sumidero (Autodesk Fusion 360 design; units mm, degrees)
part number: 2026-11-08-17-53-29-984
part number: 2026-11-08-17-55-23-853
part number: 2026-11-08-18-24-42-982
part number: 2026-11-08-18-26-39-460
part number: 2026-11-11-10-27-06-678
Autodesk Fusion 360 part; units mm, degrees
(part 1 of 2)
sketch "Sk_Exterior" plane through (0, 0, 0) normal (0, 0, 1) x (1, 0, 0) in component "Caja"
  line L0 (-70, -44) -> (70, -44)
  line L1 (70, -44) -> (70, 44)
  line L2 (70, 44) -> (-70, 44)
  line L3 (-70, 44) -> (-70, -44)
  dimension "d106" = 140
  dimension "d107" = 88
  dimension "d108" = 70
  dimension "d109" = 44
  measures "d106" horizontal distance of L0.start L0.end
  measures "d107" vertical distance of L0.start L2.end
  measures "d108" horizontal distance of origin L0.start
  measures "d109" vertical distance of origin L0.start
extrude "Ext_Cuerpo" add sketch "Sk_Exterior" along normal blind 95 makes body 1 in component "Caja"
fillet "Fillet_Exterior" radius 3 4 edges at (-70, 44, 47.5) (70, 44, 47.5) (70, -44, 47.5) (-70, -44, 47.5) on bodies 1 in component "Caja"
ref_plane "WorkPlane1" through (0, 0, 4) normal (0, 0, 1) x (1, 0, 0) in component "Caja"
sketch "Sk_Cavidad" plane through (0, 0, 4) normal (0, 0, 1) x (1, 0, 0) in component "Caja"
  line L0 (-65, -39) -> (65, -39)
  line L1 (65, -39) -> (65, 39)
  line L2 (65, 39) -> (-65, 39)
  line L3 (-65, 39) -> (-65, -39)
  dimension "d116" = 130
  dimension "d117" = 78
  dimension "d118" = 65
  dimension "d119" = 39
  measures "d116" horizontal distance of L0.start L0.end
  measures "d117" vertical distance of L0.start L2.end
  measures "d118" horizontal distance of origin L0.start
  measures "d119" vertical distance of origin L0.start
extrude "Cut_Cavidad" cut sketch "Sk_Cavidad" along normal blind 91 bodies 1 in component "Caja"
fillet "Fillet_Cavidad" radius 3 4 edges at (65, 39, 49.5) (-65, 39, 49.5) (65, -39, 49.5) (-65, -39, 49.5) on bodies 1 in component "Caja"
ref_plane "WorkPlane2" through (0, 0, 95) normal (0, 0, 1) x (1, 0, 0) in component "Caja"
sketch "Sk_Junta" plane through (0, 0, 95) normal (0, 0, 1) x (1, 0, 0) in component "Caja"
  line L0 (-68.8, -42.8) -> (68.8, -42.8)
  line L1 (68.8, -42.8) -> (68.8, 42.8)
  line L2 (68.8, 42.8) -> (-68.8, 42.8)
  line L3 (-68.8, 42.8) -> (-68.8, -42.8)
  line L4 (-66.2, -40.2) -> (66.2, -40.2)
  line L5 (66.2, -40.2) -> (66.2, 40.2)
  line L6 (66.2, 40.2) -> (-66.2, 40.2)
  line L7 (-66.2, 40.2) -> (-66.2, -40.2)
  dimension "d126" = 137.6
  dimension "d127" = 85.6
  dimension "d128" = 68.8
  dimension "d129" = 42.8
  dimension "d130" = 132.4
  dimension "d131" = 80.4
  dimension "d132" = 66.2
  dimension "d133" = 40.2
  measures "d126" horizontal distance of L0.start L0.end
  measures "d127" vertical distance of L0.start L2.end
  measures "d128" horizontal distance of origin L0.start
  measures "d129" vertical distance of origin L0.start
  measures "d130" horizontal distance of L4.start L4.end
  measures "d131" vertical distance of L4.start L6.end
  measures "d132" horizontal distance of origin L4.start
  measures "d133" vertical distance of origin L4.start
extrude "Cut_Junta" cut sketch "Sk_Junta" against normal blind 1.5 bodies 1 in component "Caja"
fillet "Fillet_Junta" radius 3.6 4 edges at (68.8, -42.8, 94.25) (-68.8, -42.8, 94.25) (68.8, 42.8, 94.25) (-68.8, 42.8, 94.25) on bodies 1 in component "Caja"
fillet "Fillet_Junta" radius 1 4 edges at (66.2, 40.2, 94.25) (-66.2, 40.2, 94.25) (66.2, -40.2, 94.25) (-66.2, -40.2, 94.25) on bodies 1 in component "Caja"
sketch "Sk_Oreja_1" plane through (0, 0, 0) normal (0, 0, 1) x (1, 0, 0) in component "Caja"
  line L0 (58, 43) -> (70, 43)
  line L1 (70, 43) -> (70, 56)
  line L2 (70, 56) -> (58, 56)
  line L3 (58, 56) -> (58, 43)
  dimension "d140" = 12
  dimension "d141" = 13
  dimension "d142" = 58
  dimension "d143" = 43
  measures "d140" horizontal distance of L0.start L0.end
  measures "d141" vertical distance of L0.start L2.end
  measures "d142" horizontal distance of origin L0.start
  measures "d143" vertical distance of origin L0.start
extrude "Oreja_1" add sketch "Sk_Oreja_1" along normal blind 95 bodies 1 in component "Caja"
sketch "Sk_Oreja_2" plane through (0, 0, 0) normal (0, 0, 1) x (1, 0, 0) in component "Caja"
  line L0 (58, -56) -> (70, -56)
  line L1 (70, -56) -> (70, -43)
  line L2 (70, -43) -> (58, -43)
  line L3 (58, -43) -> (58, -56)
  dimension "d146" = 12
  dimension "d147" = 13
  dimension "d148" = 58
  dimension "d149" = 56
  measures "d146" horizontal distance of L0.start L0.end
  measures "d147" vertical distance of L0.start L2.end
  measures "d148" horizontal distance of origin L0.start
  measures "d149" vertical distance of origin L0.start
extrude "Oreja_2" add sketch "Sk_Oreja_2" along normal blind 95 bodies 1 in component "Caja"
sketch "Sk_Oreja_3" plane through (0, 0, 0) normal (0, 0, 1) x (1, 0, 0) in component "Caja"
  line L0 (-70, 43) -> (-58, 43)
  line L1 (-58, 43) -> (-58, 56)
  line L2 (-58, 56) -> (-70, 56)
  line L3 (-70, 56) -> (-70, 43)
  dimension "d152" = 12
  dimension "d153" = 13
  dimension "d154" = 70
  dimension "d155" = 43
  measures "d152" horizontal distance of L0.start L0.end
  measures "d153" vertical distance of L0.start L2.end
  measures "d154" horizontal distance of origin L0.start
  measures "d155" vertical distance of origin L0.start
extrude "Oreja_3" add sketch "Sk_Oreja_3" along normal blind 95 bodies 1 in component "Caja"
sketch "Sk_Oreja_4" plane through (0, 0, 0) normal (0, 0, 1) x (1, 0, 0) in component "Caja"
  line L0 (-70, -56) -> (-58, -56)
  line L1 (-58, -56) -> (-58, -43)
  line L2 (-58, -43) -> (-70, -43)
  line L3 (-70, -43) -> (-70, -56)
  dimension "d158" = 12
  dimension "d159" = 13
  dimension "d160" = 70
  dimension "d161" = 56
  measures "d158" horizontal distance of L0.start L0.end
  measures "d159" vertical distance of L0.start L2.end
  measures "d160" horizontal distance of origin L0.start
  measures "d161" vertical distance of origin L0.start
extrude "Oreja_4" add sketch "Sk_Oreja_4" along normal blind 95 bodies 1 in component "Caja"
sketch "Sk_Inserto_1" plane through (0, 0, 95) normal (0, 0, 1) x (1, 0, 0) in component "Caja"
  circle A0 centre (64, 50) radius 2.3
  dimension "d164" = 4.6
  dimension "d165" = 64
  dimension "d166" = 50
  measures "d164" diameter of A0
  measures "d165" horizontal distance of origin A0.centre
  measures "d166" vertical distance of origin A0.centre
extrude "Inserto_1" cut sketch "Sk_Inserto_1" against normal blind 6 bodies 1 in component "Caja"
sketch "Sk_Inserto_2" plane through (0, 0, 95) normal (0, 0, 1) x (1, 0, 0) in component "Caja"
  circle A0 centre (64, -50) radius 2.3
  dimension "d169" = 4.6
  dimension "d170" = 64
  dimension "d171" = 50
  measures "d169" diameter of A0
  measures "d170" horizontal distance of origin A0.centre
  measures "d171" vertical distance of origin A0.centre
extrude "Inserto_2" cut sketch "Sk_Inserto_2" against normal blind 6 bodies 1 in component "Caja"
sketch "Sk_Inserto_3" plane through (0, 0, 95) normal (0, 0, 1) x (1, 0, 0) in component "Caja"
  circle A0 centre (-64, 50) radius 2.3
  dimension "d174" = 4.6
  dimension "d175" = 64
  dimension "d176" = 50
  measures "d174" diameter of A0
  measures "d175" horizontal distance of origin A0.centre
  measures "d176" vertical distance of origin A0.centre
extrude "Inserto_3" cut sketch "Sk_Inserto_3" against normal blind 6 bodies 1 in component "Caja"
sketch "Sk_Inserto_4" plane through (0, 0, 95) normal (0, 0, 1) x (1, 0, 0) in component "Caja"
  circle A0 centre (-64, -50) radius 2.3
  dimension "d179" = 4.6
  dimension "d180" = 64
  dimension "d181" = 50
  measures "d179" diameter of A0
  measures "d180" horizontal distance of origin A0.centre
  measures "d181" vertical distance of origin A0.centre
extrude "Inserto_4" cut sketch "Sk_Inserto_4" against normal blind 6 bodies 1 in component "Caja"
ref_plane "WorkPlane1" through (0, 0, -10) normal (0, 0, 1) x (1, 0, 0) in component "Referencias"
sketch "Sk_Rejilla" plane through (0, 0, -10) normal (0, 0, 1) x (1, 0, 0) in component "Referencias"
  line L0 (-330, -205) -> (330, -205)
  line L1 (330, -205) -> (330, 205)
  line L2 (330, 205) -> (-330, 205)
  line L3 (-330, 205) -> (-330, -205)
  dimension "d462" = 660
  dimension "d463" = 410
  dimension "d464" = 330
  dimension "d465" = 205
  measures "d462" horizontal distance of L0.start L0.end
  measures "d463" vertical distance of L0.start L2.end
  measures "d464" horizontal distance of origin L0.start
  measures "d465" vertical distance of origin L0.start
extrude "Rejilla_placa" add sketch "Sk_Rejilla" along normal blind 10 separate body makes body 2 in component "Referencias"
sketch "Sk_Ranura" plane through (0, 0, 0) normal (0, 0, 1) x (1, 0, 0) in component "Referencias"
  line L0 (-290, -192) -> (-265, -192)
  line L1 (-265, -192) -> (-265, -72)
  line L2 (-265, -72) -> (-290, -72)
  line L3 (-290, -72) -> (-290, -192)
  dimension "d468" = 25
  dimension "d469" = 120
  dimension "d470" = 290
  dimension "d471" = 192
  measures "d468" horizontal distance of L0.start L0.end
  measures "d469" vertical distance of L0.start L2.end
  measures "d470" horizontal distance of origin L0.start
  measures "d471" vertical distance of origin L0.start
extrude "Cut_Ranura" cut sketch "Sk_Ranura" against normal blind 10 bodies 2 in component "Referencias"
pattern_linear "Patron_Ranuras" count 16 spacing 37 along (1, 0, 0) count 3 spacing 132 along (0, 1, 0) of "Cut_Ranura" in component "Referencias"
ref_plane "WorkPlane2" through (0, 0, -18) normal (0, 0, 1) x (1, 0, 0) in component "Referencias"
ref_plane "WorkPlane3" through (0, 0, -19.6) normal (0, 0, 1) x (1, 0, 0) in component "Referencias"
ref_plane "WorkPlane4" through (0, 0, -14) normal (0, 0, 1) x (1, 0, 0) in component "Referencias"
ref_plane "WorkPlane5" through (0, 0, -132) normal (0, 0, 1) x (1, 0, 0) in component "Referencias"
sketch "Sk_Sonda" plane through (0, 0, -132) normal (0, 0, 1) x (1, 0, 0) in component "Referencias"
  circle A0 centre (0, 0) radius 11
  dimension "d504" = 22
  constraint vertical A0.centre origin
  constraint horizontal A0.centre origin
  measures "d504" diameter of A0
extrude "Sonda_f" add sketch "Sk_Sonda" along normal blind 17 separate body makes body 3 in component "Referencias"
sketch "Sk_Sonda_Cara" plane through (0, 0, -132) normal (0, 0, 1) x (1, 0, 0) in component "Referencias"
  circle A0 centre (0, 0) radius 9
  dimension "d507" = 18
  constraint vertical A0.centre origin
  constraint horizontal A0.centre origin
  measures "d507" diameter of A0
extrude "Sonda_rebaje_cara" cut sketch "Sk_Sonda_Cara" along normal blind 1 bodies 3 in component "Referencias"
extrude "Sonda_membrana" add sketch "Sk_Sonda_Cara" along normal blind 1 separate body makes body 4 in component "Referencias"
sketch "Sk_Cono" plane through (0, 0, 0) normal (0, 1, 0) x (1, 0, 0) in component "Referencias"
  line L0 (0, 132) -> (0, 532)
  line L1 (0, 532) -> (186.5231, 532)
  line L2 (186.5231, 532) -> (0, 132)
  dimension "d512" = 132
  dimension "d513" = 400
  dimension "d514" = 25
  constraint vertical L0
  constraint vertical origin L0.start
  constraint perpendicular L0 L1
  measures "d512" vertical distance of origin L0.start
  measures "d513" distance of L0.start L0.end
  measures "d514" angle of L0 L2
revolve "Cono_vision_f" add sketch "Sk_Cono" angle 360 about axis through (0, 0, -132) along (0, 0, -1) separate body makes body 5 in component "Referencias"
sketch "Sk_Placa" plane through (0, 0, 0) normal (0, 0, 1) x (1, 0, 0) in component "Tapa"
  line L0 (-70, -44) -> (70, -44)
  line L1 (70, -44) -> (70, 44)
  line L2 (70, 44) -> (-70, 44)
  line L3 (-70, 44) -> (-70, -44)
  dimension "d540" = 140
  dimension "d541" = 88
  dimension "d542" = 70
  dimension "d543" = 44
  measures "d540" horizontal distance of L0.start L0.end
  measures "d541" vertical distance of L0.start L2.end
  measures "d542" horizontal distance of origin L0.start
  measures "d543" vertical distance of origin L0.start
extrude "Placa" add sketch "Sk_Placa" along normal blind 4 separate body makes body 6 in component "Tapa"
fillet "Fillet_Placa" radius 3 4 edges at (-70, 44, 2) (70, 44, 2) (70, -44, 2) (-70, -44, 2) on bodies 6 in component "Tapa"
sketch "Sk_Oreja_1 (2)" plane through (0, 0, 0) normal (0, 0, 1) x (1, 0, 0) in component "Tapa"
  line L0 (58, 43) -> (70, 43)
  line L1 (70, 43) -> (70, 56)
  line L2 (70, 56) -> (58, 56)
  line L3 (58, 56) -> (58, 43)
  dimension "d548" = 12
  dimension "d549" = 13
  dimension "d550" = 58
  dimension "d551" = 43
  measures "d548" horizontal distance of L0.start L0.end
  measures "d549" vertical distance of L0.start L2.end
  measures "d550" horizontal distance of origin L0.start
  measures "d551" vertical distance of origin L0.start
extrude "Oreja_1'" add sketch "Sk_Oreja_1 (2)" along normal blind 4 bodies 6 in component "Tapa"
sketch "Sk_Oreja_2 (2)" plane through (0, 0, 0) normal (0, 0, 1) x (1, 0, 0) in component "Tapa"
  line L0 (58, -56) -> (70, -56)
  line L1 (70, -56) -> (70, -43)
  line L2 (70, -43) -> (58, -43)
  line L3 (58, -43) -> (58, -56)
  dimension "d554" = 12
  dimension "d555" = 13
  dimension "d556" = 58
  dimension "d557" = 56
  measures "d554" horizontal distance of L0.start L0.end
  measures "d555" vertical distance of L0.start L2.end
  measures "d556" horizontal distance of origin L0.start
  measures "d557" vertical distance of origin L0.start
extrude "Oreja_2'" add sketch "Sk_Oreja_2 (2)" along normal blind 4 bodies 6 in component "Tapa"
sketch "Sk_Oreja_3 (2)" plane through (0, 0, 0) normal (0, 0, 1) x (1, 0, 0) in component "Tapa"
  line L0 (-70, 43) -> (-58, 43)
  line L1 (-58, 43) -> (-58, 56)
  line L2 (-58, 56) -> (-70, 56)
  line L3 (-70, 56) -> (-70, 43)
  dimension "d560" = 12
  dimension "d561" = 13
  dimension "d562" = 70
  dimension "d563" = 43
  measures "d560" horizontal distance of L0.start L0.end
  measures "d561" vertical distance of L0.start L2.end
  measures "d562" horizontal distance of origin L0.start
  measures "d563" vertical distance of origin L0.start
extrude "Oreja_3'" add sketch "Sk_Oreja_3 (2)" along normal blind 4 bodies 6 in component "Tapa"
sketch "Sk_Oreja_4 (2)" plane through (0, 0, 0) normal (0, 0, 1) x (1, 0, 0) in component "Tapa"
  line L0 (-70, -56) -> (-58, -56)
  line L1 (-58, -56) -> (-58, -43)
  line L2 (-58, -43) -> (-70, -43)
  line L3 (-70, -43) -> (-70, -56)
  dimension "d566" = 12
  dimension "d567" = 13
  dimension "d568" = 70
  dimension "d569" = 56
  measures "d566" horizontal distance of L0.start L0.end
  measures "d567" vertical distance of L0.start L2.end
  measures "d568" horizontal distance of origin L0.start
  measures "d569" vertical distance of origin L0.start
extrude "Oreja_4'" add sketch "Sk_Oreja_4 (2)" along normal blind 4 bodies 6 in component "Tapa"
sketch "Sk_Paso_1" plane through (0, 0, 0) normal (0, 0, 1) x (1, 0, 0) in component "Tapa"
  circle A0 centre (64, 50) radius 1.7
  dimension "d572" = 3.4
  dimension "d573" = 64
  dimension "d574" = 50
  measures "d572" diameter of A0
  measures "d573" horizontal distance of origin A0.centre
  measures "d574" vertical distance of origin A0.centre
extrude "Paso_1" cut sketch "Sk_Paso_1" along normal blind 4 bodies 6 in component "Tapa"
sketch "Sk_Paso_2" plane through (0, 0, 0) normal (0, 0, 1) x (1, 0, 0) in component "Tapa"
  circle A0 centre (64, -50) radius 1.7
  dimension "d577" = 3.4
  dimension "d578" = 64
  dimension "d579" = 50
  measures "d577" diameter of A0
  measures "d578" horizontal distance of origin A0.centre
  measures "d579" vertical distance of origin A0.centre
extrude "Paso_2" cut sketch "Sk_Paso_2" along normal blind 4 bodies 6 in component "Tapa"
sketch "Sk_Paso_3" plane through (0, 0, 0) normal (0, 0, 1) x (1, 0, 0) in component "Tapa"
  circle A0 centre (-64, 50) radius 1.7
  dimension "d582" = 3.4
  dimension "d583" = 64
  dimension "d584" = 50
  measures "d582" diameter of A0
  measures "d583" horizontal distance of origin A0.centre
  measures "d584" vertical distance of origin A0.centre
extrude "Paso_3" cut sketch "Sk_Paso_3" along normal blind 4 bodies 6 in component "Tapa"
sketch "Sk_Paso_4" plane through (0, 0, 0) normal (0, 0, 1) x (1, 0, 0) in component "Tapa"
  circle A0 centre (-64, -50) radius 1.7
  dimension "d587" = 3.4
  dimension "d588" = 64
  dimension "d589" = 50
  measures "d587" diameter of A0
  measures "d588" horizontal distance of origin A0.centre
  measures "d589" vertical distance of origin A0.centre
extrude "Paso_4" cut sketch "Sk_Paso_4" along normal blind 4 bodies 6 in component "Tapa"
ref_plane "WorkPlane1" through (0, 0, 4) normal (0, 0, 1) x (1, 0, 0) in component "Tapa"
sketch "Sk_Flecha" plane through (0, 0, 4) normal (0, 0, 1) x (1, 0, 0) in component "Tapa"
  line L0 (-23, 0) -> (-33, 5)
  line L1 (-33, 5) -> (-33, 2)
  line L2 (-33, 2) -> (-47, 2)
  line L3 (-47, 2) -> (-47, -2)
  line L4 (-47, -2) -> (-33, -2)
  line L5 (-33, -2) -> (-33, -5)
  line L6 (-33, -5) -> (-23, 0)
extrude "Flecha" add sketch "Sk_Flecha" along normal blind 1 bodies 6 in component "Tapa"
ref_plane "WorkPlane5" through (0, 0, 8) normal (0, 0, 1) x (1, 0, 0) in component "Caja"
sketch "Sk_Pestana_1" plane through (0, 0, 0) normal (0, 0, 1) x (1, 0, 0) in component "Caja"
  line L0 (41, 43) -> (59, 43)
  line L1 (59, 43) -> (59, 63)
  line L2 (59, 63) -> (41, 63)
  line L3 (41, 63) -> (41, 43)
  dimension "d671" = 18
  dimension "d672" = 20
  dimension "d673" = 41
  dimension "d674" = 43
  measures "d671" horizontal distance of L0.start L0.end
  measures "d672" vertical distance of L0.start L2.end
  measures "d673" horizontal distance of origin L0.start
  measures "d674" vertical distance of origin L0.start
extrude "Pestana_1" add sketch "Sk_Pestana_1" along normal blind 8 bodies 1 in component "Caja"
sketch "Sk_Pestana_2" plane through (0, 0, 0) normal (0, 0, 1) x (1, 0, 0) in component "Caja"
  line L0 (41, -63) -> (59, -63)
  line L1 (59, -63) -> (59, -43)
  line L2 (59, -43) -> (41, -43)
  line L3 (41, -43) -> (41, -63)
  dimension "d677" = 18
  dimension "d678" = 20
  dimension "d679" = 41
  dimension "d680" = 63
  measures "d677" horizontal distance of L0.start L0.end
  measures "d678" vertical distance of L0.start L2.end
  measures "d679" horizontal distance of origin L0.start
  measures "d680" vertical distance of origin L0.start
extrude "Pestana_2" add sketch "Sk_Pestana_2" along normal blind 8 bodies 1 in component "Caja"
sketch "Sk_Pestana_3" plane through (0, 0, 0) normal (0, 0, 1) x (1, 0, 0) in component "Caja"
  line L0 (-59, 43) -> (-41, 43)
  line L1 (-41, 43) -> (-41, 63)
  line L2 (-41, 63) -> (-59, 63)
  line L3 (-59, 63) -> (-59, 43)
  dimension "d683" = 18
  dimension "d684" = 20
  dimension "d685" = 59
  dimension "d686" = 43
  measures "d683" horizontal distance of L0.start L0.end
  measures "d684" vertical distance of L0.start L2.end
  measures "d685" horizontal distance of origin L0.start
  measures "d686" vertical distance of origin L0.start
extrude "Pestana_3" add sketch "Sk_Pestana_3" along normal blind 8 bodies 1 in component "Caja"
sketch "Sk_Pestana_4" plane through (0, 0, 0) normal (0, 0, 1) x (1, 0, 0) in component "Caja"
  line L0 (-59, -63) -> (-41, -63)
  line L1 (-41, -63) -> (-41, -43)
  line L2 (-41, -43) -> (-59, -43)
  line L3 (-59, -43) -> (-59, -63)
  dimension "d689" = 18
  dimension "d690" = 20
  dimension "d691" = 59
  dimension "d692" = 63
  measures "d689" horizontal distance of L0.start L0.end
  measures "d690" vertical distance of L0.start L2.end
  measures "d691" horizontal distance of origin L0.start
  measures "d692" vertical distance of origin L0.start
extrude "Pestana_4" add sketch "Sk_Pestana_4" along normal blind 8 bodies 1 in component "Caja"
sketch "Sk_PernoPest_1" plane through (0, 0, 0) normal (0, 0, 1) x (1, 0, 0) in component "Caja"
  circle A0 centre (50, 54) radius 3.25
  dimension "d695" = 6.5
  dimension "d696" = 50
  dimension "d697" = 54
  measures "d695" diameter of A0
  measures "d696" horizontal distance of origin A0.centre
  measures "d697" vertical distance of origin A0.centre
extrude "PernoPest_1" cut sketch "Sk_PernoPest_1" along normal blind 8 bodies 1 in component "Caja"
sketch "Sk_PernoPest_2" plane through (0, 0, 0) normal (0, 0, 1) x (1, 0, 0) in component "Caja"
  circle A0 centre (50, -54) radius 3.25
  dimension "d700" = 6.5
  dimension "d701" = 50
  dimension "d702" = 54
  measures "d700" diameter of A0
  measures "d701" horizontal distance of origin A0.centre
  measures "d702" vertical distance of origin A0.centre
extrude "PernoPest_2" cut sketch "Sk_PernoPest_2" along normal blind 8 bodies 1 in component "Caja"
sketch "Sk_PernoPest_3" plane through (0, 0, 0) normal (0, 0, 1) x (1, 0, 0) in component "Caja"
  circle A0 centre (-50, 54) radius 3.25
  dimension "d705" = 6.5
  dimension "d706" = 50
  dimension "d707" = 54
  measures "d705" diameter of A0
  measures "d706" horizontal distance of origin A0.centre
  measures "d707" vertical distance of origin A0.centre
extrude "PernoPest_3" cut sketch "Sk_PernoPest_3" along normal blind 8 bodies 1 in component "Caja"
sketch "Sk_PernoPest_4" plane through (0, 0, 0) normal (0, 0, 1) x (1, 0, 0) in component "Caja"
  circle A0 centre (-50, -54) radius 3.25
  dimension "d710" = 6.5
  dimension "d711" = 50
  dimension "d712" = 54
  measures "d710" diameter of A0
  measures "d711" horizontal distance of origin A0.centre
  measures "d712" vertical distance of origin A0.centre
extrude "PernoPest_4" cut sketch "Sk_PernoPest_4" along normal blind 8 bodies 1 in component "Caja"
sketch "Sk_HexPest_1" plane through (0, 0, 8) normal (0, 0, 1) x (1, 0, 0) in component "Caja"
  line L0 (55.2, 53.0022) -> (50, 56.0044)
  line L1 (50, 56.0044) -> (44.8, 53.0022)
  line L2 (44.8, 53.0022) -> (44.8, 46.9978)
  line L3 (44.8, 46.9978) -> (50, 43.9956)
  line L4 (50, 43.9956) -> (55.2, 46.9978)
  line L5 (55.2, 46.9978) -> (55.2, 53.0022)
  point P0 (50, 50)
extrude "HexPest_1" cut sketch "Sk_HexPest_1" against normal blind 5 bodies 1 in component "Caja"
sketch "Sk_HexPest_2" plane through (0, 0, 8) normal (0, 0, 1) x (1, 0, 0) in component "Caja"
  line L0 (55.2, -46.9978) -> (50, -43.9956)
  line L1 (50, -43.9956) -> (44.8, -46.9978)
  line L2 (44.8, -46.9978) -> (44.8, -53.0022)
  line L3 (44.8, -53.0022) -> (50, -56.0044)
  line L4 (50, -56.0044) -> (55.2, -53.0022)
  line L5 (55.2, -53.0022) -> (55.2, -46.9978)
  point P0 (50, -50)
extrude "HexPest_2" cut sketch "Sk_HexPest_2" against normal blind 5 bodies 1 in component "Caja"
sketch "Sk_HexPest_3" plane through (0, 0, 8) normal (0, 0, 1) x (1, 0, 0) in component "Caja"
  line L0 (-44.8, 53.0022) -> (-50, 56.0044)
  line L1 (-50, 56.0044) -> (-55.2, 53.0022)
  line L2 (-55.2, 53.0022) -> (-55.2, 46.9978)
  line L3 (-55.2, 46.9978) -> (-50, 43.9956)
  line L4 (-50, 43.9956) -> (-44.8, 46.9978)
  line L5 (-44.8, 46.9978) -> (-44.8, 53.0022)
  point P0 (-50, 50)
extrude "HexPest_3" cut sketch "Sk_HexPest_3" against normal blind 5 bodies 1 in component "Caja"
sketch "Sk_HexPest_4" plane through (0, 0, 8) normal (0, 0, 1) x (1, 0, 0) in component "Caja"
  line L0 (-44.8, -46.9978) -> (-50, -43.9956)
  line L1 (-50, -43.9956) -> (-55.2, -46.9978)
  line L2 (-55.2, -46.9978) -> (-55.2, -53.0022)
  line L3 (-55.2, -53.0022) -> (-50, -56.0044)
  line L4 (-50, -56.0044) -> (-44.8, -53.0022)
  line L5 (-44.8, -53.0022) -> (-44.8, -46.9978)
  point P0 (-50, -50)
extrude "HexPest_4" cut sketch "Sk_HexPest_4" against normal blind 5 bodies 1 in component "Caja"
ref_plane "WorkPlane1" through (0, 0, 8) normal (0, 0, 1) x (1, 0, 0) in component "Barra_superior"
sketch "Sk_Barra_1" plane through (0, 0, 0) normal (0, 0, 1) x (1, 0, 0) in component "Barra_superior"
  line L0 (-70, 39) -> (70, 39)
  line L1 (70, 39) -> (70, 69)
  line L2 (70, 69) -> (-70, 69)
  line L3 (-70, 69) -> (-70, 39)
  dimension "d725" = 140
  dimension "d726" = 30
  dimension "d727" = 70
  dimension "d728" = 39
  measures "d725" horizontal distance of L0.start L0.end
  measures "d726" vertical distance of L0.start L2.end
  measures "d727" horizontal distance of origin L0.start
  measures "d728" vertical distance of origin L0.start
extrude "Barra_1" add sketch "Sk_Barra_1" along normal blind 8 separate body makes body 7 in component "Barra_superior"
fillet "Fillet_Barra_1" radius 3 4 edges at (-70, 69, 4) (70, 69, 4) (70, 39, 4) (-70, 39, 4) on bodies 7 in component "Barra_superior"
sketch "Sk_Perno_1_1" plane through (0, 0, 8) normal (0, 0, 1) x (1, 0, 0) in component "Barra_superior"
  circle A0 centre (50, 54) radius 3.25
  dimension "d733" = 6.5
  dimension "d734" = 50
  dimension "d735" = 54
  measures "d733" diameter of A0
  measures "d734" horizontal distance of origin A0.centre
  measures "d735" vertical distance of origin A0.centre
extrude "Perno_1_1" cut sketch "Sk_Perno_1_1" against normal blind 8 bodies 7 in component "Barra_superior"
sketch "Sk_Perno_1_2" plane through (0, 0, 8) normal (0, 0, 1) x (1, 0, 0) in component "Barra_superior"
  circle A0 centre (-50, 54) radius 3.25
  dimension "d738" = 6.5
  dimension "d739" = 50
  dimension "d740" = 54
  measures "d738" diameter of A0
  measures "d739" horizontal distance of origin A0.centre
  measures "d740" vertical distance of origin A0.centre
extrude "Perno_1_2" cut sketch "Sk_Perno_1_2" against normal blind 8 bodies 7 in component "Barra_superior"
sketch "Sk_Barra_2" plane through (0, 0, 0) normal (0, 0, 1) x (1, 0, 0) in component "Barra_superior"
  line L0 (-70, -69) -> (70, -69)
  line L1 (70, -69) -> (70, -39)
  line L2 (70, -39) -> (-70, -39)
  line L3 (-70, -39) -> (-70, -69)
  dimension "d743" = 140
  dimension "d744" = 30
  dimension "d745" = 70
  dimension "d746" = 69
  measures "d743" horizontal distance of L0.start L0.end
  measures "d744" vertical distance of L0.start L2.end
  measures "d745" horizontal distance of origin L0.start
  measures "d746" vertical distance of origin L0.start
extrude "Barra_2" add sketch "Sk_Barra_2" along normal blind 8 separate body makes body 8 in component "Barra_superior"
fillet "Fillet_Barra_2" radius 3 4 edges at (-70, -39, 4) (70, -39, 4) (70, -69, 4) (-70, -69, 4) on bodies 8 in component "Barra_superior"
sketch "Sk_Perno_2_1" plane through (0, 0, 8) normal (0, 0, 1) x (1, 0, 0) in component "Barra_superior"
  circle A0 centre (50, -54) radius 3.25
  dimension "d751" = 6.5
  dimension "d752" = 50
  dimension "d753" = 54
  measures "d751" diameter of A0
  measures "d752" horizontal distance of origin A0.centre
  measures "d753" vertical distance of origin A0.centre
extrude "Perno_2_1" cut sketch "Sk_Perno_2_1" against normal blind 8 bodies 8 in component "Barra_superior"
sketch "Sk_Perno_2_2" plane through (0, 0, 8) normal (0, 0, 1) x (1, 0, 0) in component "Barra_superior"
  circle A0 centre (-50, -54) radius 3.25
  dimension "d756" = 6.5
  dimension "d757" = 50
  dimension "d758" = 54
  measures "d756" diameter of A0
  measures "d757" horizontal distance of origin A0.centre
  measures "d758" vertical distance of origin A0.centre
extrude "Perno_2_2" cut sketch "Sk_Perno_2_2" against normal blind 8 bodies 8 in component "Barra_superior"
sketch "Sk_Ranura_Conector" plane through (0, 0, 4) normal (0, 0, 1) x (1, 0, 0) in component "Tapa"
  line L0 (45, -3.5) -> (59, -3.5)
  line L1 (59, -3.5) -> (59, 3.5)
  line L2 (59, 3.5) -> (45, 3.5)
  line L3 (45, 3.5) -> (45, -3.5)
  dimension "d779" = 14
  dimension "d780" = 7
  dimension "d781" = 45
  dimension "d782" = 3.5
  measures "d779" horizontal distance of L0.start L0.end
  measures "d780" vertical distance of L0.start L2.end
  measures "d781" horizontal distance of origin L0.start
  measures "d782" vertical distance of origin L0.start
extrude "Ranura_Conector" cut sketch "Sk_Ranura_Conector" against normal blind 4 bodies 6 in component "Tapa"
ref_plane "WorkPlane3" through (0, 0, 3) normal (0, 0, 1) x (1, 0, 0) in component "Tapa"
sketch "Sk_Collarin" plane through (0, 0, 3) normal (0, 0, 1) x (1, 0, 0) in component "Tapa"
  circle A0 centre (52, 0) radius 15
  circle A1 centre (52, 0) radius 11
  dimension "d787" = 30
  dimension "d788" = 52
  dimension "d789" = 22
  constraint horizontal origin A0.centre
  constraint coincident A0.centre A1.centre
  measures "d787" diameter of A0
  measures "d788" horizontal distance of origin A0.centre
  measures "d789" diameter of A1
extrude "Collarin" add sketch "Sk_Collarin" along normal blind 22 separate body makes body 9 in component "Tapa"
combine "Unir_Collarin" operation add target body 6 tool bodies 9 in component "Tapa"
ref_plane "WorkPlane6" through (0, 0, -18) normal (0, 0, 1) x (1, 0, 0) in component "Referencias"
sketch "Sk_Perfboard" plane through (0, 0, -18) normal (0, 0, 1) x (1, 0, 0) in component "Referencias"
  line L0 (-61, -35) -> (-1, -35)
  line L1 (-1, -35) -> (-1, 5)
  line L2 (-1, 5) -> (-61, 5)
  line L3 (-61, 5) -> (-61, -35)
  dimension "d794" = 60
  dimension "d795" = 40
  dimension "d796" = 61
  dimension "d797" = 35
  measures "d794" horizontal distance of L0.start L0.end
  measures "d795" vertical distance of L0.start L2.end
  measures "d796" horizontal distance of origin L0.start
  measures "d797" vertical distance of origin L0.start
extrude "Perfboard_placa" add sketch "Sk_Perfboard" against normal blind 1.6 separate body makes body 10 in component "Referencias"
ref_plane "WorkPlane7" through (0, 0, -19.6) normal (0, 0, 1) x (1, 0, 0) in component "Referencias"
sketch "Sk_Componentes" plane through (0, 0, -19.6) normal (0, 0, 1) x (1, 0, 0) in component "Referencias"
  line L0 (-61, -35) -> (-1, -35)
  line L1 (-1, -35) -> (-1, 5)
  line L2 (-1, 5) -> (-61, 5)
  line L3 (-61, 5) -> (-61, -35)
  dimension "d802" = 60
  dimension "d803" = 40
  dimension "d804" = 61
  dimension "d805" = 35
  measures "d802" horizontal distance of L0.start L0.end
  measures "d803" vertical distance of L0.start L2.end
  measures "d804" horizontal distance of origin L0.start
  measures "d805" vertical distance of origin L0.start
extrude "Componentes_vol" add sketch "Sk_Componentes" against normal blind 36.4 separate body makes body 11 in component "Referencias"
sketch "Sk_Modulo" plane through (0, 0, -18) normal (0, 0, 1) x (1, 0, 0) in component "Referencias"
  line L0 (-61, 6) -> (-20, 6)
  line L1 (-20, 6) -> (-20, 34.5)
  line L2 (-20, 34.5) -> (-61, 34.5)
  line L3 (-61, 34.5) -> (-61, 6)
  dimension "d808" = 41
  dimension "d809" = 28.5
  dimension "d810" = 61
  dimension "d811" = 6
  measures "d808" horizontal distance of L0.start L0.end
  measures "d809" vertical distance of L0.start L2.end
  measures "d810" horizontal distance of origin L0.start
  measures "d811" vertical distance of origin L0.start
extrude "Modulo_sensor_f" add sketch "Sk_Modulo" against normal blind 19 separate body makes body 12 in component "Referencias"
ref_plane "WorkPlane8" through (0, 0, -105) normal (0, 0, 1) x (1, 0, 0) in component "Referencias"
sketch "Sk_Powerbank" plane through (0, 0, -105) normal (0, 0, 1) x (1, 0, 0) in component "Referencias"
  line L0 (-61, -35) -> (39, -35)
  line L1 (39, -35) -> (39, 35)
  line L2 (39, 35) -> (-61, 35)
  line L3 (-61, 35) -> (-61, -35)
  dimension "d816" = 100
  dimension "d817" = 70
  dimension "d818" = 61
  dimension "d819" = 35
  measures "d816" horizontal distance of L0.start L0.end
  measures "d817" vertical distance of L0.start L2.end
  measures "d818" horizontal distance of origin L0.start
  measures "d819" vertical distance of origin L0.start
extrude "Powerbank_f" add sketch "Sk_Powerbank" along normal blind 25 separate body makes body 13 in component "Referencias"
move_body "Mover_sonda_a_collarin" bodies 3 4 5 to x (1, 0, 0) y (0, 1, 0) z (0, 0, 1) at (52, 0, 0) in component "Referencias"
component "Caja" placed x (1, 0, 0) y (0, -1, 0) z (0, 0, -1) at (0, 0, -10)
component "Referencias" placed x (1, 0, 0) y (0, 1, 0) z (0, 0, 1) at (0, 0, 0)
component "Tapa" placed x (1, 0, 0) y (0, -1, 0) z (0, 0, -1) at (0, 0, -105)
component "Barra_superior" placed x (1, 0, 0) y (0, 1, 0) z (0, 0, 1) at (0, 0, 0)
hidden bodies 2 5 10 11 12 13
equation "perfboard_largo = 60 mm" comment "[Componentes]"
equation "perfboard_ancho = 40 mm" comment "[Componentes]"
equation "perfboard_espesor = 1.6 mm" comment "[Componentes]"
equation "altura_conjunto_montado = 38 mm" comment "[Componentes] perfboard + componentes + pines"
equation "modulo_sensor_largo = 41 mm" comment "[Componentes]"
equation "modulo_sensor_ancho = 28.5 mm" comment "[Componentes]"
equation "modulo_sensor_ancho_headers = 33.5 mm" comment "[Componentes] ancho con headers"
equation "modulo_sensor_alto = 19 mm" comment "[Componentes]"
equation "sonda_diametro_agujero = 22 mm" comment "[Componentes]"
equation "sonda_longitud = 17 mm" comment "[Componentes]"
equation "cable_sensor_largo = 2500 mm" comment "[Componentes] no se modela"
equation "holgura_interna = 4 mm" comment "[Caja]"
equation "cavidad_largo = powerbank_largo + espacio_conector_bateria + 2 * holgura_interna" comment "[Caja]"
equation "cavidad_ancho = powerbank_ancho + 2 * holgura_interna" comment "[Caja]"
equation "cavidad_alto = holgura_interna + altura_conjunto_montado + espacio_cableado + powerbank_alto + holgura_interna" comment "[Caja]"
equation "pared = 5 mm" comment "[Caja]"
equation "piso = 4 mm" comment "[Caja]"
equation "espesor_tapa = 4 mm" comment "[Caja]"
equation "radio_esquinas = 3 mm" comment "[Caja]"
equation "caja_ext_largo = cavidad_largo + 2 * pared" comment "[Caja] derivado"
equation "caja_ext_ancho = cavidad_ancho + 2 * pared" comment "[Caja] derivado"
equation "caja_alto_total = piso + cavidad_alto" comment "[Caja] derivado"
equation "junta_ranura_ancho = 2.6 mm" comment "[Junta]"
equation "junta_ranura_prof = 1.5 mm" comment "[Junta]"
equation "junta_cordon_diametro = 2 mm" comment "[Junta]"
equation "junta_radio_int = 1 mm" comment "[Junta] radio esquina interior de la ranura"
equation "junta_largo_ext = cavidad_largo + pared + junta_ranura_ancho" comment "[Junta] derivado"
equation "junta_ancho_ext = cavidad_ancho + pared + junta_ranura_ancho" comment "[Junta] derivado"
equation "junta_largo_int = cavidad_largo + pared - junta_ranura_ancho" comment "[Junta] derivado"
equation "junta_ancho_int = cavidad_ancho + pared - junta_ranura_ancho" comment "[Junta] derivado"
equation "tornillos_tapa = 4" comment "[Tapa] cantidad M3"
equation "diametro_insertos_termicos = insert_od - 0.4 mm" comment "[Tapa]"
equation "profundidad_insertos = insert_largo + holgura_fondo_insert" comment "[Tapa]"
equation "agujero_paso_tapa = 3.4 mm" comment "[Tapa]"
equation "oreja_lado = 12 mm" comment "[Tapa] lado de la oreja"
equation "oreja_solape = 1 mm" comment "[Tapa] solape oreja-pared"
equation "oreja_cx = caja_ext_largo / 2 - oreja_lado / 2" comment "[Tapa] derivado"
equation "oreja_cy = caja_ext_ancho / 2 + oreja_lado / 2" comment "[Tapa] derivado"
equation "prensaestopas_USB_agujero = 15 mm" comment "[Prensaestopas] PG9"
equation "prensaestopas_sensor_agujero = 12.5 mm" comment "[Prensaestopas] PG7"
equation "prensaestopas_separacion = 28 mm" comment "[Prensaestopas] min 25 entre centros"
equation "gland_z = piso + cavidad_alto / 2" comment "[Prensaestopas] altura media de la cavidad"
equation "refuerzo_prensa_espesor = 2 mm" comment "[Prensaestopas]"
equation "refuerzo_prensa_margen = 12 mm" comment "[Prensaestopas] margen alrededor de los agujeros"
equation "refuerzo_prensa_ancho = prensaestopas_separacion + 2 * refuerzo_prensa_margen" comment "[Prensaestopas] derivado"
equation "refuerzo_prensa_alto = 2 * refuerzo_prensa_margen" comment "[Prensaestopas] derivado"
equation "poste_alto = holgura_interna" comment "[Interior]"
equation "poste_diametro = 6 mm" comment "[Interior]"
equation "poste_agujero = 2.5 mm" comment "[Interior]"
equation "poste_margen = 4 mm" comment "[Interior] desde las esquinas de la perfboard"
equation "margen_perfboard = holgura_interna" comment "[Interior] separacion perfboard-pared"
equation "separacion_modulos = 1 mm" comment "[Interior] perfboard-modulo sensor"
equation "riel_alto = 2 mm" comment "[Interior]"
equation "riel_ancho = 1.6 mm" comment "[Interior]"
equation "tolerancia_ajuste = 0.2 mm" comment "[Interior] tolerancia de encaje"
equation "pb_cx = -cavidad_largo / 2 + margen_perfboard + perfboard_largo / 2" comment "[Interior] derivado: centro X perfboard"
equation "sensor_x0 = pb_cx - perfboard_largo / 2" comment "[Interior] derivado: borde X del modulo sensor"
equation "poste_x1 = pb_cx - ( perfboard_largo / 2 - poste_margen )" comment "[Interior] derivado"
equation "poste_x2 = pb_cx + ( perfboard_largo / 2 - poste_margen )" comment "[Interior] derivado"
equation "poste_y = perfboard_ancho / 2 - poste_margen" comment "[Interior] derivado"
equation "riel_izq_x = sensor_x0 - tolerancia_ajuste - riel_ancho" comment "[Interior] derivado"
equation "riel_der_x = sensor_x0 + modulo_sensor_ancho_headers + tolerancia_ajuste" comment "[Interior] derivado"
equation "rejilla_largo = 660 mm" comment "[Rejilla]"
equation "rejilla_ancho = 410 mm" comment "[Rejilla]"
equation "ranura_ancho = 25 mm" comment "[Rejilla] [MEDIR]"
equation "ranura_largo = 120 mm" comment "[Rejilla] [MEDIR]"
equation "barrote_ancho = 12 mm" comment "[Rejilla] [MEDIR]"
equation "separacion_pernos = 100 mm" comment "[Rejilla] [MEDIR] centro a centro entre ranuras de pernos"
equation "rejilla_espesor = 10 mm" comment "[Rejilla] [ASUMIDO] solo para la referencia"
equation "rejilla_cols = 16" comment "[Rejilla] columnas de ranuras (referencia)"
equation "rejilla_filas = 3" comment "[Rejilla] filas de ranuras (referencia)"
equation "rejilla_paso_x = ranura_ancho + barrote_ancho" comment "[Rejilla] derivado"
equation "rejilla_paso_y = ranura_largo + barrote_ancho" comment "[Rejilla] derivado"
equation "perno_agujero = 6.5 mm" comment "[Pernos] M6 paso"
equation "pernos_x = separacion_pernos / 2" comment "[Pernos] derivado"
equation "perno_reborde_alto = 2 mm" comment "[Pernos] reborde de silicona"
equation "perno_reborde_diam_int = 11 mm" comment "[Pernos]"
equation "perno_reborde_diam_ext = 15 mm" comment "[Pernos]"
equation "barra_largo = separacion_pernos + 40 mm" comment "[Barra]"
equation "barra_ancho = 30 mm" comment "[Barra]"
equation "barra_espesor = 8 mm" comment "[Barra]"
equation "chaflan_sonda = 0.5 mm" comment "[Barra]"
equation "canal_cable_ancho = 8 mm" comment "[Barra]"
equation "tuerca_hex_cara = 10.4 mm" comment "[Barra] M6 (10 mm entre caras + 0.4)"
equation "tuerca_hex_prof = 5 mm" comment "[Barra]"
equation "cono_vision_angulo = 50 deg" comment "[Referencias]"
equation "cono_vision_largo = 400 mm" comment "[Referencias]"
equation "flecha_largo = 24 mm" comment "[Tapa]"
equation "flecha_ancho = 10 mm" comment "[Tapa]"
equation "flecha_alto = 1 mm" comment "[Tapa]"
equation "d106 = caja_ext_largo"
equation "d107 = caja_ext_ancho"
equation "d108 = caja_ext_largo / 2"
equation "d109 = caja_ext_ancho / 2"
equation "d110 = caja_alto_total"
equation "d113 = radio_esquinas"
equation "d114 = piso"
equation "d116 = cavidad_largo"
equation "d117 = cavidad_ancho"
equation "d118 = cavidad_largo / 2"
equation "d119 = cavidad_ancho / 2"
equation "d120 = cavidad_alto"
equation "d123 = radio_esquinas"
equation "d124 = caja_alto_total"
equation "d126 = junta_largo_ext"
equation "d127 = junta_ancho_ext"
equation "d128 = junta_largo_ext / 2"
equation "d129 = junta_ancho_ext / 2"
equation "d130 = junta_largo_int"
equation "d131 = junta_ancho_int"
equation "d132 = junta_largo_int / 2"
equation "d133 = junta_ancho_int / 2"
equation "d134 = -( junta_ranura_prof )"
equation "d137 = junta_radio_int + junta_ranura_ancho"
equation "d139 = junta_radio_int"
equation "d140 = oreja_lado"
equation "d141 = oreja_lado + oreja_solape"
equation "d142 = caja_ext_largo / 2 - oreja_lado"
equation "d143 = caja_ext_ancho / 2 - oreja_solape"
equation "d144 = caja_alto_total"
equation "d146 = oreja_lado"
equation "d147 = oreja_lado + oreja_solape"
equation "d148 = caja_ext_largo / 2 - oreja_lado"
equation "d149 = caja_ext_ancho / 2 + oreja_lado"
equation "d150 = caja_alto_total"
equation "d152 = oreja_lado"
equation "d153 = oreja_lado + oreja_solape"
equation "d154 = caja_ext_largo / 2"
equation "d155 = caja_ext_ancho / 2 - oreja_solape"
equation "d156 = caja_alto_total"
equation "d158 = oreja_lado"
equation "d159 = oreja_lado + oreja_solape"
equation "d160 = caja_ext_largo / 2"
equation "d161 = caja_ext_ancho / 2 + oreja_lado"
equation "d162 = caja_alto_total"
equation "d164 = diametro_insertos_termicos"
equation "d165 = oreja_cx"
equation "d166 = oreja_cy"
equation "d167 = -( profundidad_insertos )"
equation "d169 = diametro_insertos_termicos"
equation "d170 = oreja_cx"
equation "d171 = oreja_cy"
equation "d172 = -( profundidad_insertos )"
equation "d174 = diametro_insertos_termicos"
equation "d175 = oreja_cx"
equation "d176 = oreja_cy"
equation "d177 = -( profundidad_insertos )"
equation "d179 = diametro_insertos_termicos"
equation "d180 = oreja_cx"
equation "d181 = oreja_cy"
equation "d182 = -( profundidad_insertos )"
equation "sonda_cara_diametro = 18 mm" comment "[Referencias] cara emisora de la sonda"
equation "sonda_cara_prof = 1 mm" comment "[Referencias] profundidad del rebaje de la cara emisora"
equation "sonda_holgura_cable = 6 mm" comment "[Sonda] espacio entre el fondo del collarin y la parte trasera de la sonda (salida del cable)"
equation "sonda_sobresale = 2 mm" comment "[Sonda] cuanto sobresale la cara emisora del collarin"
equation "collar_pared = 4 mm" comment "[Sonda] pared del collarin"
equation "collar_alto = sonda_longitud + sonda_holgura_cable - sonda_sobresale" comment "[Sonda] derivado"
equation "collar_diam_ext = sonda_diametro_agujero + 2 * collar_pared" comment "[Sonda] derivado"
equation "collar_muesca_alto = sonda_holgura_cable + 2 mm" comment "[Sonda] muesca para el cable"
equation "tapa_gland_x = 32 mm" comment "[Tapa] posicion X de los prensaestopas"
equation "tapa_flecha_x = -35 mm" comment "[Tapa] posicion X de la flecha"
equation "d460 = -rejilla_espesor"
equation "d462 = rejilla_largo"
equation "d463 = rejilla_ancho"
equation "d464 = rejilla_largo / 2"
equation "d465 = rejilla_ancho / 2"
equation "d466 = rejilla_espesor"
equation "d468 = ranura_ancho"
equation "d469 = ranura_largo"
equation "d470 = rejilla_paso_x * ( rejilla_cols - 1 ) / 2 + ranura_ancho / 2"
equation "d471 = rejilla_paso_y * ( rejilla_filas - 1 ) / 2 + ranura_largo / 2"
equation "d472 = -( rejilla_espesor )"
equation "d474 = rejilla_cols"
equation "d475 = rejilla_filas"
equation "d476 = rejilla_paso_x"
equation "d477 = rejilla_paso_y"
equation "d478 = -( rejilla_espesor + piso + poste_alto )"
equation "d486 = -( rejilla_espesor + piso + poste_alto + perfboard_espesor )"
equation "d494 = -( rejilla_espesor + piso )"
equation "d502 = -( rejilla_espesor + caja_alto_total + espesor_tapa + sonda_holgura_cable + sonda_longitud )"
equation "d504 = sonda_diametro_agujero"
equation "d505 = sonda_longitud"
equation "d507 = sonda_cara_diametro"
equation "d508 = sonda_cara_prof"
equation "d510 = sonda_cara_prof"
equation "d512 = rejilla_espesor + caja_alto_total + espesor_tapa + sonda_holgura_cable + sonda_longitud"
equation "d513 = cono_vision_largo"
equation "d514 = cono_vision_angulo / 2"
equation "d540 = caja_ext_largo"
equation "d541 = caja_ext_ancho"
equation "d542 = caja_ext_largo / 2"
equation "d543 = caja_ext_ancho / 2"
equation "d544 = espesor_tapa"
equation "d547 = radio_esquinas"
equation "d548 = oreja_lado"
equation "d549 = oreja_lado + oreja_solape"
equation "d550 = caja_ext_largo / 2 - oreja_lado"
equation "d551 = caja_ext_ancho / 2 - oreja_solape"
equation "d552 = espesor_tapa"
equation "d554 = oreja_lado"
equation "d555 = oreja_lado + oreja_solape"
equation "d556 = caja_ext_largo / 2 - oreja_lado"
equation "d557 = caja_ext_ancho / 2 + oreja_lado"
equation "d558 = espesor_tapa"
equation "d560 = oreja_lado"
equation "d561 = oreja_lado + oreja_solape"
equation "d562 = caja_ext_largo / 2"
equation "d563 = caja_ext_ancho / 2 - oreja_solape"
equation "d564 = espesor_tapa"
equation "d566 = oreja_lado"
equation "d567 = oreja_lado + oreja_solape"
equation "d568 = caja_ext_largo / 2"
equation "d569 = caja_ext_ancho / 2 + oreja_lado"
equation "d570 = espesor_tapa"
equation "d572 = agujero_paso_tapa"
equation "d573 = oreja_cx"
equation "d574 = oreja_cy"
equation "d575 = espesor_tapa"
equation "d577 = agujero_paso_tapa"
equation "d578 = oreja_cx"
equation "d579 = oreja_cy"
equation "d580 = espesor_tapa"
equation "d582 = agujero_paso_tapa"
equation "d583 = oreja_cx"
equation "d584 = oreja_cy"
equation "d585 = espesor_tapa"
equation "d587 = agujero_paso_tapa"
equation "d588 = oreja_cx"
equation "d589 = oreja_cy"
equation "d590 = espesor_tapa"
equation "d592 = espesor_tapa"
equation "d622 = flecha_alto"
equation "sonda_cable_agujero = 6 mm" comment "[Sonda] paso del cable por la tapa, dentro del collarin (se sella con silicona/epoxi)"
equation "pestana_ancho = 18 mm" comment "[Anclaje] ancho de cada pestana lateral"
equation "pestana_pos_y = 54 mm" comment "[Anclaje] distancia del eje de los pernos al centro de la caja (en Y)"
equation "pestana_espesor = 8 mm" comment "[Anclaje] espesor de la pestana"
equation "d669 = pestana_espesor"
equation "d671 = pestana_ancho"
equation "d672 = pestana_pos_y + pestana_ancho / 2 - caja_ext_ancho / 2 + oreja_solape"
equation "d673 = pernos_x - pestana_ancho / 2"
equation "d674 = caja_ext_ancho / 2 - oreja_solape"
equation "d675 = pestana_espesor"
equation "d677 = pestana_ancho"
equation "d678 = pestana_pos_y + pestana_ancho / 2 - caja_ext_ancho / 2 + oreja_solape"
equation "d679 = pernos_x - pestana_ancho / 2"
equation "d680 = pestana_pos_y + pestana_ancho / 2"
equation "d681 = pestana_espesor"
equation "d683 = pestana_ancho"
equation "d684 = pestana_pos_y + pestana_ancho / 2 - caja_ext_ancho / 2 + oreja_solape"
equation "d685 = pernos_x + pestana_ancho / 2"
equation "d686 = caja_ext_ancho / 2 - oreja_solape"
equation "d687 = pestana_espesor"
equation "d689 = pestana_ancho"
equation "d690 = pestana_pos_y + pestana_ancho / 2 - caja_ext_ancho / 2 + oreja_solape"
equation "d691 = pernos_x + pestana_ancho / 2"
equation "d692 = pestana_pos_y + pestana_ancho / 2"
equation "d693 = pestana_espesor"
equation "d695 = perno_agujero"
equation "d696 = pernos_x"
equation "d697 = pestana_pos_y"
equation "d698 = pestana_espesor"
equation "d700 = perno_agujero"
equation "d701 = pernos_x"
equation "d702 = pestana_pos_y"
equation "d703 = pestana_espesor"
equation "d705 = perno_agujero"
equation "d706 = pernos_x"
equation "d707 = pestana_pos_y"
equation "d708 = pestana_espesor"
equation "d710 = perno_agujero"
equation "d711 = pernos_x"
equation "d712 = pestana_pos_y"
equation "d713 = pestana_espesor"
equation "d715 = -( tuerca_hex_prof )"
equation "d717 = -( tuerca_hex_prof )"
equation "d719 = -( tuerca_hex_prof )"
equation "d721 = -( tuerca_hex_prof )"
equation "d723 = barra_espesor"
equation "d725 = barra_largo"
equation "d726 = barra_ancho"
equation "d727 = barra_largo / 2"
equation "d728 = pestana_pos_y - barra_ancho / 2"
equation "d729 = barra_espesor"
equation "d732 = radio_esquinas"
equation "d733 = perno_agujero"
equation "d734 = pernos_x"
equation "d735 = pestana_pos_y"
equation "d736 = -( barra_espesor )"
equation "d738 = perno_agujero"
equation "d739 = pernos_x"
equation "d740 = pestana_pos_y"
equation "d741 = -( barra_espesor )"
equation "d743 = barra_largo"
equation "d744 = barra_ancho"
equation "d745 = barra_largo / 2"
equation "d746 = pestana_pos_y + barra_ancho / 2"
equation "d747 = barra_espesor"
equation "d750 = radio_esquinas"
equation "d751 = perno_agujero"
equation "d752 = pernos_x"
equation "d753 = pestana_pos_y"
equation "d754 = -( barra_espesor )"
equation "d756 = perno_agujero"
equation "d757 = pernos_x"
equation "d758 = pestana_pos_y"
equation "d759 = -( barra_espesor )"
equation "insert_od = 5 mm" comment "[Insertos M3] diametro exterior del inserto de laton"
equation "insert_largo = 4 mm" comment "[Insertos M3] largo del inserto"
equation "holgura_fondo_insert = 2 mm" comment "[Insertos M3] espacio al fondo para el plastico desplazado"
equation "powerbank_largo = 100 mm" comment "[Bateria]"
equation "powerbank_ancho = 70 mm" comment "[Bateria]"
equation "powerbank_alto = 25 mm" comment "[Bateria]"
equation "espacio_cableado = 20 mm" comment "[Interior] espacio vertical entre el montaje del ESP32 y la bateria para el cableado"
equation "espacio_conector_bateria = 22 mm" comment "[Interior] largo extra en un extremo para el conector USB de la bateria y el codo del cable"
equation "sonda_conector_ancho = 14 mm" comment "[Sonda] ranura para el conector del cable del sensor (USB-A ~12 mm + holgura)"
equation "sonda_conector_alto = 7 mm" comment "[Sonda] ranura para el conector del cable del sensor (USB-A ~4.5 mm + holgura)"
equation "collar_x = cavidad_largo / 2 - 13 mm" comment "[Sonda] posicion X del collarin (extremo libre de la tapa, fuera de la huella de la bateria)"
equation "pb_cy = -cavidad_ancho / 2 + holgura_interna + perfboard_ancho / 2" comment "[Interior] derivado: centro Y del montaje ESP32"
equation "modulo_y0 = pb_cy + perfboard_ancho / 2 + separacion_modulos" comment "[Interior] derivado: borde Y del modulo del sensor"
equation "d779 = sonda_conector_ancho"
equation "d780 = sonda_conector_alto"
equation "d781 = collar_x - sonda_conector_ancho / 2"
equation "d782 = sonda_conector_alto / 2"
equation "d783 = -( espesor_tapa )"
equation "d785 = espesor_tapa - 1 mm"
equation "d787 = collar_diam_ext"
equation "d788 = collar_x"
equation "d789 = sonda_diametro_agujero"
equation "d790 = collar_alto + 1 mm"
equation "d792 = -( rejilla_espesor + piso + poste_alto )"
equation "d794 = perfboard_largo"
equation "d795 = perfboard_ancho"
equation "d796 = -pb_cx + perfboard_largo / 2"